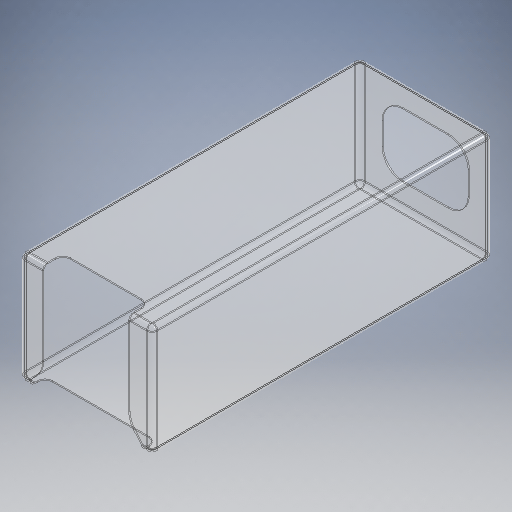
# Autodesk Inventor part: Shrink Wrap
Saved by Autodesk Inventor 2025 (Build 290162010, 162A)
## iProperties
Created: 2025-08-20
Part Number: Shrink Wrap
Material: Polycarbonate, Clear
Document SubType Name: Modeling
Designer: Glen Collingwood
Density: 1.2 g/cm^3
Appearance: Polycarbonate - Clear
Author: Glen Collingwood
Autodesk Inventor part; units mm, degrees
ref_plane "YZ Plane" through (0, 0, 0) normal (1, 0, 0) x (0, 1, 0)
ref_plane "XZ Plane" through (0, 0, 0) normal (0, 1, 0) x (-1, 0, 0)
ref_plane "XY Plane" through (0, 0, 0) normal (0, 0, 1) x (1, 0, 0)
sketch "Sketch1" plane through (0, 0, 0) normal (1, 0, 0) x (0, 1, 0)
  line L0 (22, 67.25) -> (-22, 67.25)
  line L1 (-22, 67.25) -> (-22, -67.25)
  line L2 (-22, -67.25) -> (22, -67.25)
  line L3 (22, -67.25) -> (22, 67.25)
  line L4 (22, 67.25) -> (-22, -67.25) construction
  line L5 (-22, 67.25) -> (22, -67.25) construction
  point P0 (0, 0)
  point P1 (0, 0)
  dimension "d0" = 134.5
  dimension "d1" = 44
  constraints: 12 end point, 2 midpoint, 2 parallel, 1 coincident, 1 horizontal, 1 perpendicular
  measures "d0" distance of L2.end L0.start
  measures "d1" distance of L1.end L2.end
extrude "Extrusion1" add sketch "Sketch1" along normal mid plane 52.5
fillet "Fillet1" radius 2.25 4 edges at (26.25, 0, 67.25) (-26.25, 0, 67.25) (-26.25, 0, -67.25) (26.25, 0, -67.25)
fillet "Fillet2" radius 2 16 edges at (25.591, 22, 66.591) (0, 22, 67.25) (-25.591, 22, 66.591) (-26.25, 22, 0) (-25.591, 22, -66.591) (0, 22, -67.25) (25.591, 22, -66.591) (26.25, 22, 0) (25.591, -22, -66.591) (0, -22, -67.25) (-25.591, -22, -66.591) (-26.25, -22, 0) (-25.591, -22, 66.591) (0, -22, 67.25) (25.591, -22, 66.591) (26.25, -22, 0)
shell "Shell1" thickness 0.5 removed faces 0
sketch "Sketch2" plane through (-24, -20, 67.25) normal (0, 0, 1) x (1, 0, 0)
  line L0 (15, 32.5) -> (33, 32.5)
  line L1 (41, 24.5) -> (41, 15.5)
  line L2 (33, 7.5) -> (15, 7.5)
  line L3 (7, 15.5) -> (7, 24.5)
  line L4 (7, 32.5) -> (41, 7.5) construction
  line L5 (41, 32.5) -> (7, 7.5) construction
  arc A0 (15, 32.5) -> (7, 24.5) centre (15, 24.5) ccw
  arc A1 (41, 24.5) -> (33, 32.5) centre (33, 24.5) ccw
  arc A2 (7, 15.5) -> (15, 7.5) centre (15, 15.5) ccw
  arc A3 (33, 7.5) -> (41, 15.5) centre (33, 15.5) ccw
  point P0 (24, 20)
  dimension "d7" = 25
  dimension "d8" = 34
  dimension "d9" = 8
  constraints: 12 end point, 8 point on circle, 8 point on line, 8 tangent, 4 centre point, 3 equal radius, 2 midpoint, 2 parallel, 1 horizontal, 1 perpendicular
  measures "d7" distance of L5.start L4.end
  measures "d8" distance of L4.end L5.end
  measures "d9" radius of A0
extrude "Extrusion2" cut sketch "Sketch2" against normal through all
sketch "Sketch3" plane through (-24, -20, 67.25) normal (0, 0, 1) x (1, 0, 0)
  arc A0 (15, 32.5) -> (7, 24.5) centre (15, 24.5) ccw projected
  line L0 (7, 24.5) -> (7, 15.5) projected
  arc A1 (7, 15.5) -> (15, 7.5) centre (15, 15.5) ccw projected
  line L1 (15, 7.5) -> (33, 7.5) projected
  arc A2 (33, 7.5) -> (41, 15.5) centre (33, 15.5) ccw projected
  line L2 (41, 15.5) -> (41, 24.5) projected
  arc A3 (41, 24.5) -> (33, 32.5) centre (33, 24.5) ccw projected
  line L3 (33, 32.5) -> (15, 32.5) projected
  line L4 (48, 0) -> (0, 0) projected
  line L5 (0, 0) -> (0, 40) projected
  line L6 (0, 40) -> (48, 40) projected
  line L7 (48, 40) -> (48, 0) projected
  line L8 (7, 24.5) -> (41, 24.5)
  line L9 (41, 24.5) -> (41, 42)
  line L10 (41, 42) -> (7, 42)
  line L11 (7, 42) -> (7, 24.5)
  line L12 (48, 42) -> (0, 42) projected
  point P0 (24, 20)
  constraints: 8 end point, 2 collinear, 2 parallel, 1 horizontal, 1 perpendicular
extrude "Extrusion3" cut sketch "Sketch3" against normal blind 8 contours L3 A3 L8 A0 | A0 L11 L6 L9 A3 L3 | L11 L10 L9 L6
fillet "Fillet3" radius 3 2 edges at (-17, 21.75, 59.25) (17, 21.75, 59.25)
sketch "Sketch4" plane through (-24, -20, 67.25) normal (0, 0, 1) x (1, 0, 0)
  line L0 (7, 40) -> (7, 15.5) projected
  arc A0 (7, 15.5) -> (15, 7.5) centre (15, 15.5) ccw projected
  line L1 (15, 7.5) -> (33, 7.5) projected
  arc A1 (33, 7.5) -> (41, 15.5) centre (33, 15.5) ccw projected
  line L2 (41, 15.5) -> (41, 40) projected
  line L3 (41, 40) -> (48, 40) projected
  line L4 (48, 40) -> (48, 0) projected
  line L5 (48, 0) -> (0, 0) projected
  line L6 (0, 0) -> (0, 40) projected
  line L7 (0, 40) -> (7, 40) projected
  line L8 (7, 15.5) -> (7, 6)
  line L9 (7, 6) -> (1.9654, 0)
  line L10 (1.9654, 0) -> (1.9654, -2)
  line L11 (0, -2) -> (48, -2) projected
  line L12 (41, 15.5) -> (41, 6)
  line L13 (41, 6) -> (46.0346, 0)
  line L14 (46.0346, -2) -> (46.0346, 0)
  point P0 (24, 20)
  dimension "d15" = 8
  dimension "d16" = 50
  dimension "d17" = 50
  constraints: 12 end point, 4 point on line, 1 collinear, 1 horizontal alignment, 1 parallel, 1 perpendicular, 1 point on circle, 1 vertical
  measures "d15" distance from line of L11 L8.end
  measures "d16" angle of L5 L9
  measures "d17" angle of L5 L13
extrude "Extrusion4" cut sketch "Sketch4" against normal blind 6 contours A0 L1 A1 L12 L13 L5 L9 L8 | L5 L14 L11 L10
fillet "Fillet4" radius 3 2 edges at (-22.0346, -21.75, 61.25) (22.0346, -21.75, 61.25)
fillet "Fillet5" radius 8 2 edges at (-17, -14, 67) (17, -14, 67)
equation "\"d17\" = d16"
body "Solid1"
